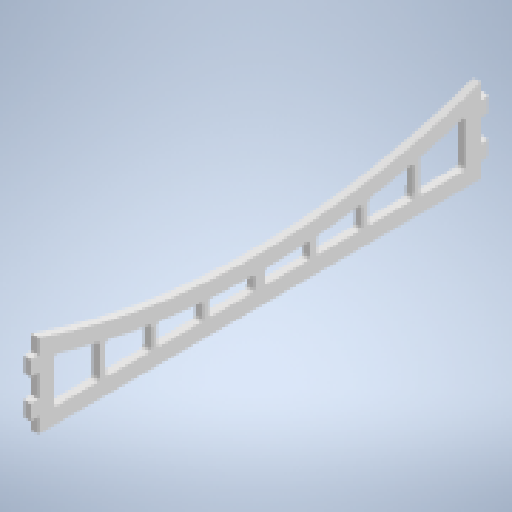
# Autodesk Inventor part: StandMain
Saved by Autodesk Inventor 2025.2 (Build 292293000, 293)
## iProperties
Created: 2025-07-03
Part Number: StandMain
Material: Generic
Document SubType Name: Modeling
Designer: ricoa
Density: 1 g/cm^3
Appearance: Default
Author: ricoa
Autodesk Inventor part; units mm, degrees
ref_plane "YZ Plane" through (0, 0, 0) normal (1, 0, 0) x (0, 1, 0)
ref_plane "XZ Plane" through (0, 0, 0) normal (0, 1, 0) x (-1, 0, 0)
ref_plane "XY Plane" through (0, 0, 0) normal (0, 0, 1) x (1, 0, 0)
sketch "Sketch1" plane through (0, 0, 0) normal (0, 0, 1) x (1, 0, 0)
  line L0 (15, 25) -> (-15, 25) projected
  line L1 (18, -30) -> (18, 20) projected
  line L2 (18, 20) -> (15, 25) projected
  line L3 (-15, 25) -> (-18, 20) projected
  line L4 (-18, 20) -> (-18, -30) projected
  line L5 (-18, -30) -> (18, -30) projected
  line L6 (2.5, -25) -> (2.5, 25)
  line L7 (2.5, 25) -> (-2.5, 25)
  line L8 (-2.5, 25) -> (-2.5, -25)
  line L9 (-2.5, -25) -> (2.5, 25) construction
  line L10 (2.5, -25) -> (-2.5, 25) construction
  line L11 (2.5, -25) -> (2.5, -30)
  line L12 (-2.5, -25) -> (-2.5, -30)
  point P0 (0, 0)
  dimension "d6" = 5
  constraints: 14 end point, 3 point on line, 2 midpoint, 2 perpendicular, 1 parallel
  measures "d6" distance of L7.end L6.end
extrude "Extrusion1" add sketch "Sketch1" along normal blind 301 contours L6 L11 L5 L12 L8 L0
sketch "Sketch2" plane through (2.5, -30, 0) normal (1, 0, 0) x (0, 0, -1)
  line L0 (0, 0) -> (0, 55) projected
  line L1 (0, 55) -> (-5, 55)
  line L2 (0, 55) -> (-301, 55) projected
  line L3 (-5, 55) -> (-5, 45)
  line L4 (-5, 45) -> (0, 45)
  line L5 (0, 45) -> (0, 35)
  line L6 (0, 35) -> (-5, 35)
  line L7 (-5, 35) -> (-5, 20)
  line L8 (-5, 20) -> (0, 20)
  line L9 (0, 20) -> (0, 10)
  line L10 (0, 10) -> (-5, 10)
  line L11 (-5, 10) -> (-5, 0)
  line L12 (-5, 0) -> (0, 0)
  line L13 (-150.5, 55) -> (-150.5, 0)
  line L14 (0, 0) -> (-301, 0) projected
  line L15 (-301, 0) -> (-301, 55)
  line L16 (-301, 55) -> (-296, 55)
  line L17 (-296, 55) -> (-296, 45)
  line L18 (-296, 45) -> (-301, 45)
  line L19 (-301, 45) -> (-301, 35)
  line L20 (-301, 35) -> (-296, 35)
  line L21 (-296, 35) -> (-296, 20)
  line L22 (-296, 20) -> (-301, 20)
  line L23 (-301, 20) -> (-301, 10)
  line L24 (-301, 10) -> (-296, 10)
  line L25 (-296, 10) -> (-296, 0)
  line L26 (-296, 0) -> (-301, 0)
  point P0 (0, 30)
  point P1 (-301, 30)
  point P2 (-296, 0)
  point P3 (0, 20)
  dimension "d7" = 5
  dimension "d8" = 10
  dimension "d9" = 10
  dimension "d10" = 15
  dimension "d11" = 10
  dimension "d12" = 10
  constraints: 48 end point, 15 point on line, 13 symmetric about line, 7 perpendicular, 2 midpoint
  measures "d7" distance of L0.end L1.end
  measures "d8" distance of L1.end L3.end
  measures "d9" distance of L4.end L5.end
  measures "d10" distance of L6.end L7.end
  measures "d11" distance of L8.end L9.end
  measures "d12" distance of L10.end L11.end
extrude "Extrusion2" cut sketch "Sketch2" against normal blind 301 contours L12 L11 L10 L0 | L8 L7 L6 L0 | L14 L15 L24 L25 | L4 L3 L1 L0 | L17 L18 L15 L2 | L15 L20 L21 L22
sketch "Sketch3" plane through (2.5, -20, 0) normal (1, 0, 0) x (0, 0, -1)
  line L0 (-5, 45) -> (-296, 45) projected
  line L1 (-150.5, 45) -> (-150.5, 560.3875) construction
  arc A0 (-296, 45) -> (-5, 45) centre (-150.5, 455.905) ccw
  point P0 (0, 20)
  constraints: 2 end point, 2 point on circle, 1 centre point, 1 midpoint, 1 vertical
extrude "Extrusion3" cut sketch "Sketch3" against normal blind 301
sketch "Sketch4" plane through (2.5, -20, 0) normal (1, 0, 0) x (0, 0, -1)
  arc A0 (-296, 45) -> (-5, 45) centre (-150.5, 455.905) ccw projected
  line L0 (-296, 45) -> (-296, 35) projected
  line L1 (-296, 35) -> (-301, 35) projected
  line L2 (-301, 25) -> (-301, 35) projected
  line L3 (-301, 25) -> (-296, 25) projected
  line L4 (-296, 25) -> (-296, 10) projected
  line L5 (-296, 10) -> (-301, 10) projected
  line L6 (-301, 0) -> (-301, 10) projected
  line L7 (-301, 0) -> (-296, 0) projected
  line L8 (-296, 0) -> (-296, -10) projected
  line L9 (-5, -10) -> (-296, -10) projected
  line L10 (-5, -10) -> (-5, 0) projected
  line L11 (-5, 0) -> (0, 0) projected
  line L12 (0, 0) -> (0, 10) projected
  line L13 (0, 10) -> (-5, 10) projected
  line L14 (-5, 10) -> (-5, 25) projected
  line L15 (-5, 25) -> (0, 25) projected
  line L16 (0, 25) -> (0, 35) projected
  line L17 (0, 35) -> (-5, 35) projected
  line L18 (-5, 35) -> (-5, 45) projected
  line L19 (-285.75, 2.25) -> (-285.75, 28.0179)
  arc A1 (-181.6105, 10.836) -> (-155.7266, 9.7806) centre (-150.5, 455.905) ccw
  line L20 (-15.25, 30.7442) -> (-15.25, 2.3822)
  line L21 (-15.25, 2.3822) -> (-15.25, 0.25)
  line L22 (-155.75, 0.25) -> (-181.75, 0.25)
  line L23 (-283.75, 0.25) -> (-257.75, 0.25)
  line L24 (-5, -10) -> (-296, -10) projected
  line L25 (-150.5, -10) -> (-150.5, 107.95) construction
  line L26 (-255.75, 0.25) -> (-251.75, 0.25)
  line L27 (-249.767, 0.25) -> (-223.7672, 0.25)
  line L28 (-221.75, 0.25) -> (-217.75, 0.25)
  line L29 (-215.75, 0.25) -> (-189.75, 0.25)
  line L30 (-187.75, 0.25) -> (-183.75, 0.25)
  line L31 (-183.75, 0.25) -> (-153.75, 0.25)
  line L32 (-255.75, 2.25) -> (-255.75, 20.7724)
  line L33 (-221.7672, 2.2671) -> (-221.866, 13.8131)
  line L34 (-251.767, 2.2329) -> (-251.9094, 18.8975)
  line L35 (-217.75, 2.25) -> (-217.75, 12.5255)
  line L36 (-183.75, 2.25) -> (-183.75, 8.8409)
  line L37 (-187.75, 2.25) -> (-187.75, 9.4721)
  line L38 (-153.75, 2.25) -> (-153.75, 7.7808)
  arc A2 (-155.75, 0.25) -> (-153.75, 2.25) centre (-155.75, 2.25) ccw
  arc A3 (-153.75, 7.7808) -> (-155.7266, 9.7806) centre (-155.75, 7.7808) ccw
  arc A4 (-183.75, 2.25) -> (-181.75, 0.25) centre (-181.75, 2.25) ccw
  arc A5 (-189.75, 0.25) -> (-187.75, 2.25) centre (-189.75, 2.25) ccw
  arc A6 (-217.75, 2.25) -> (-215.75, 0.25) centre (-215.75, 2.25) ccw
  arc A7 (-223.7672, 0.25) -> (-221.7672, 2.2671) centre (-223.7672, 2.25) ccw
  arc A8 (-251.767, 2.2329) -> (-249.767, 0.25) centre (-249.767, 2.25) ccw
  arc A9 (-285.75, 2.25) -> (-283.75, 0.25) centre (-283.75, 2.25) ccw
  arc A10 (-257.75, 0.25) -> (-255.75, 2.25) centre (-257.75, 2.25) ccw
  arc A11 (-181.6105, 10.836) -> (-183.75, 8.8409) centre (-181.75, 8.8409) ccw
  arc A12 (-215.4588, 14.5042) -> (-189.5748, 11.4644) centre (-150.5, 455.905) ccw
  arc A13 (-187.75, 9.4721) -> (-189.5748, 11.4644) centre (-189.75, 9.4721) ccw
  arc A14 (-215.4588, 14.5042) -> (-217.75, 12.5255) centre (-215.75, 12.5255) ccw
  arc A15 (-249.4659, 20.8647) -> (-223.5385, 15.769) centre (-150.5, 455.905) ccw
  arc A16 (-221.866, 13.8131) -> (-223.5385, 15.769) centre (-223.8659, 13.796) ccw
  arc A17 (-249.4659, 20.8647) -> (-251.9094, 18.8975) centre (-249.9095, 18.9146) ccw
  arc A18 (-283.1553, 29.9275) -> (-257.2714, 22.7143) centre (-150.5, 455.905) ccw
  arc A19 (-255.75, 20.7724) -> (-257.2714, 22.7143) centre (-257.75, 20.7724) ccw
  arc A20 (-283.1553, 29.9275) -> (-285.75, 28.0179) centre (-283.75, 28.0179) ccw
  arc A21 (-296, 45) -> (-5, 45) centre (-150.5, 455.905) ccw
  line L39 (-15.25, 2.25) -> (-15.25, 28.0179)
  arc A22 (-145.2734, 9.7806) -> (-119.3895, 10.836) centre (-150.5, 455.905) ccw
  line L40 (-145.25, 0.25) -> (-119.25, 0.25)
  line L41 (-17.25, 0.25) -> (-43.25, 0.25)
  line L42 (-45.25, 0.25) -> (-49.25, 0.25)
  line L43 (-51.233, 0.25) -> (-77.2328, 0.25)
  line L44 (-79.25, 0.25) -> (-83.25, 0.25)
  line L45 (-85.25, 0.25) -> (-111.25, 0.25)
  line L46 (-113.25, 0.25) -> (-117.25, 0.25)
  line L47 (-117.25, 0.25) -> (-147.25, 0.25)
  line L48 (-45.25, 2.25) -> (-45.25, 20.7724)
  line L49 (-79.2328, 2.2671) -> (-79.134, 13.8131)
  line L50 (-49.233, 2.2329) -> (-49.0906, 18.8975)
  line L51 (-83.25, 2.25) -> (-83.25, 12.5255)
  line L52 (-117.25, 2.25) -> (-117.25, 8.8409)
  line L53 (-113.25, 2.25) -> (-113.25, 9.4721)
  line L54 (-147.25, 2.25) -> (-147.25, 7.7808)
  arc A23 (-147.25, 2.25) -> (-145.25, 0.25) centre (-145.25, 2.25) ccw
  arc A24 (-145.2734, 9.7806) -> (-147.25, 7.7808) centre (-145.25, 7.7808) ccw
  arc A25 (-119.25, 0.25) -> (-117.25, 2.25) centre (-119.25, 2.25) ccw
  arc A26 (-113.25, 2.25) -> (-111.25, 0.25) centre (-111.25, 2.25) ccw
  arc A27 (-85.25, 0.25) -> (-83.25, 2.25) centre (-85.25, 2.25) ccw
  arc A28 (-79.2328, 2.2671) -> (-77.2328, 0.25) centre (-77.2328, 2.25) ccw
  arc A29 (-51.233, 0.25) -> (-49.233, 2.2329) centre (-51.233, 2.25) ccw
  arc A30 (-17.25, 0.25) -> (-15.25, 2.25) centre (-17.25, 2.25) ccw
  arc A31 (-45.25, 2.25) -> (-43.25, 0.25) centre (-43.25, 2.25) ccw
  arc A32 (-117.25, 8.8409) -> (-119.3895, 10.836) centre (-119.25, 8.8409) ccw
  arc A33 (-111.4252, 11.4644) -> (-85.5412, 14.5042) centre (-150.5, 455.905) ccw
  arc A34 (-111.4252, 11.4644) -> (-113.25, 9.4721) centre (-111.25, 9.4721) ccw
  arc A35 (-83.25, 12.5255) -> (-85.5412, 14.5042) centre (-85.25, 12.5255) ccw
  arc A36 (-77.4615, 15.769) -> (-51.5341, 20.8647) centre (-150.5, 455.905) ccw
  arc A37 (-77.4615, 15.769) -> (-79.134, 13.8131) centre (-77.1341, 13.796) ccw
  arc A38 (-49.0906, 18.8975) -> (-51.5341, 20.8647) centre (-51.0905, 18.9146) ccw
  arc A39 (-43.7286, 22.7143) -> (-17.8447, 29.9275) centre (-150.5, 455.905) ccw
  arc A40 (-43.7286, 22.7143) -> (-45.25, 20.7724) centre (-43.25, 20.7724) ccw
  arc A41 (-15.25, 28.0179) -> (-17.8447, 29.9275) centre (-17.25, 28.0179) ccw
  point P0 (0, 20)
  point P1 (-285.75, 0.25)
  point P2 (-285.75, 30.7442)
  point P3 (-255.75, 22.3422)
  point P4 (-221.8804, 15.4971)
  point P5 (-251.9311, 21.4329)
  point P6 (-217.75, 14.8475)
  point P7 (-183.75, 10.9907)
  point P8 (-187.75, 11.3077)
  point P9 (-153.75, 9.7618)
  point P10 (-45.25, 22.3422)
  point P11 (-79.1196, 15.4971)
  point P12 (-49.0689, 21.4329)
  point P13 (-83.25, 14.8475)
  point P14 (-117.25, 10.9907)
  point P15 (-113.25, 11.3077)
  point P16 (-147.25, 9.7618)
  point P17 (-15.25, 2.25)
  point P18 (-15.25, 28.0179)
  dimension "d17" = 30
  dimension "d18" = 4
  dimension "d19" = 30
  dimension "d20" = 4
  dimension "d21" = 30
  dimension "d22" = 4
  dimension "d23" = 30
  dimension "d24" = 2
  dimension "d25" = 2
  dimension "d26" = 2
  dimension "d27" = 2
  dimension "d28" = 2
  constraints: 93 point on circle, 66 end point, 64 symmetric about line, 44 point on line, 39 centre point, 28 tangent, 11 equal radius, 5 parallel, 2 vertical, 1 midpoint, 1 perpendicular, 72 other
  measures "d17" distance of point (-285.75, 0.25) L26.start
  measures "d18" distance of L26.start L26.end
  measures "d19" distance of L26.end L28.start
  measures "d20" distance of L28.start L28.end
  measures "d21" distance of L28.end L30.start
  measures "d22" distance of L30.start L30.end
  measures "d23" distance of L30.end L31.end
  measures "d24" radius of A2
  measures "d25" radius of A11
  measures "d26" radius of A13
  measures "d27" radius of A16
  measures "d28" radius of A19
extrude "Extrusion4" cut sketch "Sketch4" against normal blind 301 contours L19 A20 A18 A19 L32 A10 L23 A9 | A1 A3 L38 A2 L22 A4 L36 A11 | L20 L21 A30 L41 A31 L48 A40 A39 A41 | A8 L34 A17 A15 A16 L33 A7 L27 | A6 L35 A14 A12 A13 L37 A5 L29 | A22 A32 L52 A25 L40 A23 L54 A24 | L43 A28 L49 A37 A36 A38 L50 A29 | L45 A26 L53 A34 A33 A35 L51 A27
body "Solid1"
